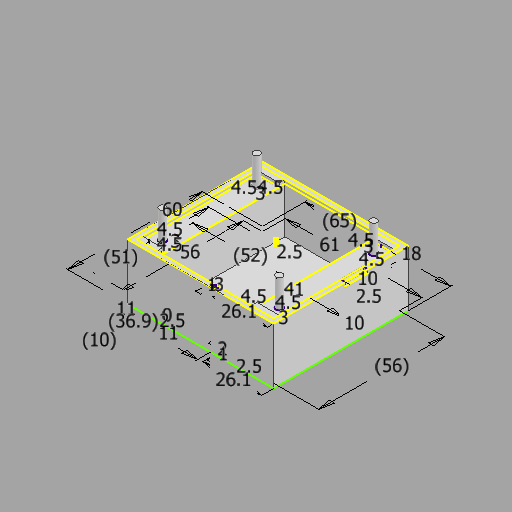
# Autodesk Inventor part: case
Saved by Autodesk Inventor 2027 (Build 310192000, 192)
## iProperties
Created: 2026-09-07
Part Number: case
Material: Generic
Document SubType Name: Modeling
Designer: jyjhm
Density: 1 g/cm^3
Appearance: Default
Author: jyjhm
Autodesk Inventor part; units mm, degrees
ref_plane "YZ Plane" through (0, 0, 0) normal (1, 0, 0) x (0, 1, 0)
ref_plane "XZ Plane" through (0, 0, 0) normal (0, 1, 0) x (-1, 0, 0)
ref_plane "XY Plane" through (0, 0, 0) normal (0, 0, 1) x (1, 0, 0)
sketch "Sketch1" plane through (0, 0, 0) normal (0, 1, 0) x (-1, 0, 0)
  line L0 (31.25, 31) -> (-29.75, 31)
  line L1 (-29.75, 31) -> (-29.75, -25)
  line L2 (-29.75, -25) -> (31.25, -25)
  line L3 (31.25, -25) -> (31.25, 31)
  line L4 (33.25, 33) -> (-31.75, 33)
  line L5 (-31.75, 33) -> (-31.75, -27)
  line L6 (-31.75, -27) -> (33.25, -27)
  line L7 (33.25, -27) -> (33.25, 33)
  line L8 (31.25, 31) -> (23.25, 31)
  line L9 (31.25, 23) -> (31.25, 31)
  line L10 (31.25, -25) -> (23.25, -25)
  line L11 (31.25, -17) -> (31.25, -25)
  line L12 (-29.75, 31) -> (-20.75, 31)
  line L13 (-29.75, 23) -> (-29.75, 31)
  line L14 (-29.75, -25) -> (-20.75, -25)
  line L15 (-29.75, -17) -> (-29.75, -25)
  line L16 (-3.65, 31) -> (-5.65, 31)
  line L17 (-5.65, 31) -> (-5.65, 32)
  line L18 (-5.65, 32) -> (-3.65, 32)
  line L19 (-3.65, 32) -> (-3.65, 31)
  line L20 (21.25, -25) -> (-19.75, -25)
  line L21 (-19.75, -25) -> (-19.75, 31)
  line L22 (-19.75, 31) -> (21.25, 31)
  line L23 (21.25, 31) -> (21.25, -25)
  line L24 (31.25, 31) -> (21.25, 31)
  line L25 (21.25, 31) -> (21.25, 28.5)
  line L26 (21.25, 28.5) -> (31.25, 28.5)
  line L27 (31.25, 28.5) -> (31.25, 31)
  line L28 (31.25, -25) -> (21.25, -25)
  line L29 (21.25, -25) -> (21.25, -22.5)
  line L30 (21.25, -22.5) -> (31.25, -22.5)
  line L31 (31.25, -22.5) -> (31.25, -25)
  line L32 (-29.75, 31) -> (-19.75, 31)
  line L33 (-19.75, 31) -> (-19.75, 28.5)
  line L34 (-19.75, 28.5) -> (-29.75, 28.5)
  line L35 (-29.75, 28.5) -> (-29.75, 31)
  line L36 (-29.75, -25) -> (-19.75, -25)
  line L37 (-19.75, -25) -> (-19.75, -22.5)
  line L38 (-19.75, -22.5) -> (-29.75, -22.5)
  line L39 (-29.75, -22.5) -> (-29.75, -25)
  line L40 (22.25, 31) -> (11.25, 31)
  line L41 (11.25, 31) -> (11.25, 33)
  line L42 (11.25, 33) -> (22.25, 33)
  line L43 (22.25, 33) -> (22.25, 31)
  line L44 (22.25, 28.5) -> (21.25, 28.5)
  line L45 (21.25, 28.5) -> (21.25, 31)
  line L46 (21.25, 31) -> (22.25, 31)
  line L47 (22.25, 31) -> (22.25, 28.5)
  point P0 (0, 0)
  point P1 (-29.75, 3)
  point P2 (21.25, 31)
  point P3 (-19.75, -25)
  point P4 (22.25, 32)
  dimension "d0" = 56
  dimension "d1" = 61
  dimension "d35" = 56
  dimension "d36" = 1
  dimension "d37" = 2
  dimension "d38" = 26.1
  dimension "d39" = 41
  dimension "d40" = 10
  dimension "d52" = 2.5
  dimension "d53" = 2.5
  dimension "d54" = 2.5
  dimension "d55" = 2.5
  dimension "d74" = 36.9
  dimension "d75" = 65
  dimension "d77" = 51
  dimension "d78" = 60
  dimension "d79" = 10
  dimension "d80" = 11
  dimension "d81" = 11
  dimension "d82" = 0
  constraints: 96 end point, 20 parallel, 14 horizontal, 10 perpendicular, 9 point on line, 2 midpoint
  measures "d0" distance of L2.end L0.start
  measures "d1" distance of L1.end L2.end
  measures "d35" distance between parallel lines of L0 L2
  measures "d36" distance of L16.end L17.end
  measures "d37" distance of L16.start L16.end
  measures "d38" distance between parallel lines of L5 L17
  measures "d39" distance between parallel lines of L21 L23
  measures "d40" distance between parallel lines of L1 L21
  measures "d52" distance between parallel lines of L0 L26
  measures "d53" distance between parallel lines of L2 L30
  measures "d54" distance between parallel lines of L0 L34
  measures "d55" distance from line of L14.end L38
  measures "d74" distance between parallel lines of L7 L19
  measures "d75" distance between parallel lines of L7 L5
  measures "d77" distance between parallel lines of L26 L30
  measures "d78" distance of L6.end L4.start
  measures "d79" distance between parallel lines of L3 L23
  measures "d80" distance from line of L7 point (22.25, 32)
  measures "d81" distance between parallel lines of L41 L43
  measures "d82" distance between parallel lines of L44 L26
extrude "Extrusion1" add sketch "Sketch1" along normal blind 3
extrude "Extrusion3" add sketch "Sketch1" along normal blind 25 contours L0 L43 L4 L7 L6 L5 L41 L19 L18 L17 L1 L2 L3 | L0 L41 L4 L43 | L0 L17 L18 L19
sketch "Sketch3" plane through (0, 25, 0) normal (0, 1, 0) x (1, 0, 0)
  line L0 (31.75, -33) -> (31.75, 27) projected
  line L1 (31.75, 27) -> (-33.25, 27) projected
  line L2 (-33.25, 27) -> (-33.25, -33) projected
  line L3 (-33.25, -33) -> (31.75, -33) projected
  line L4 (-31.25, -31) -> (-31.25, 25) projected
  line L5 (-31.25, 25) -> (29.75, 25) projected
  line L6 (29.75, 25) -> (29.75, -31) projected
  line L7 (29.75, -31) -> (-31.25, -31) projected
  line L8 (5.65, -31) -> (2.65, -31)
  line L9 (2.65, -31) -> (2.65, -32)
  line L10 (2.65, -32) -> (5.65, -32)
  line L11 (5.65, -32) -> (5.65, -31)
  line L12 (29.75, -1) -> (31.75, -1)
  line L13 (31.75, -1) -> (31.75, 9)
  line L14 (31.75, 9) -> (29.75, 9)
  line L15 (29.75, 9) -> (29.75, -1)
  point P0 (0, 0)
  point P1 (4.15, -32)
  dimension "d41" = 1
  dimension "d42" = 3
  dimension "d43" = 26.1
  dimension "d48" = 18
  dimension "d49" = 10
  constraints: 16 end point, 4 parallel, 3 point on line, 2 horizontal, 2 perpendicular, 1 midpoint
  measures "d41" distance from line of L3 point (4.15, -32)
  measures "d42" distance between parallel lines of L11 L9
  measures "d43" distance between parallel lines of L0 L11
  measures "d48" distance between parallel lines of L1 L14
  measures "d49" distance between parallel lines of L14 L12
extrude "Extrusion5" cut sketch "Sketch3" against normal blind 4 contours L11 L10 L9 L7
extrude "Extrusion6" add sketch "Sketch1" along normal blind 23.4 contours L3 L26 L47 L0 | L3 L30 L23 L26 | L47 L26 L23 L0 | L3 L2 L23 L30 | L2 L1 L38 L21 | L21 L34 L1 L0 | L38 L1 L34 L21
extrude "Extrusion7" cut sketch "Sketch3" against normal blind 1.6 contours L12 L6 L14 L0
sketch "Sketch4" plane through (0, 23.4, 0) normal (0, 1, 0) x (1, 0, 0)
  line L0 (-31.25, 25) -> (-21.25, 25) projected
  line L1 (-31.25, -31) -> (-31.25, 25) projected
  line L2 (-21.25, -31) -> (-31.25, -31) projected
  line L3 (-21.25, -31) -> (-21.25, 25) projected
  line L4 (29.75, -31) -> (19.75, -31) projected
  line L5 (29.75, -1) -> (29.75, -31) projected
  line L6 (31.75, -1) -> (29.75, -1) projected
  line L7 (31.75, 9) -> (31.75, -1) projected
  line L8 (29.75, 9) -> (31.75, 9) projected
  line L9 (29.75, 25) -> (29.75, 9) projected
  line L10 (19.75, 25) -> (29.75, 25) projected
  line L11 (19.75, 25) -> (19.75, -31) projected
  line L12 (19.75, -28.5) -> (29.75, -28.5) projected
  line L13 (-31.25, -31) -> (29.75, -31) projected
  line L14 (29.75, -31) -> (29.75, 25) projected
  line L15 (19.75, 25) -> (19.75, -31) projected
  line L16 (19.75, 22.5) -> (29.75, 22.5) projected
  line L17 (-21.25, -31) -> (-21.25, 25) projected
  line L18 (-21.25, -28.5) -> (-31.25, -28.5) projected
  line L19 (-31.25, 25) -> (-31.25, -31) projected
  line L20 (-21.25, 22.5) -> (-31.25, 22.5) projected
  line L21 (29.75, 25) -> (-31.25, 25) projected
  line L22 (-31.25, -31) -> (-21.25, -31)
  line L23 (-21.25, -31) -> (-21.25, -28.5)
  line L24 (-21.25, -28.5) -> (-31.25, -28.5)
  line L25 (-31.25, -28.5) -> (-31.25, -31)
  line L26 (-21.25, 22.5) -> (-31.25, 22.5)
  line L27 (-31.25, 22.5) -> (-31.25, 25)
  line L28 (-31.25, 25) -> (-21.25, 25)
  line L29 (-21.25, 25) -> (-21.25, 22.5)
  line L30 (19.75, -28.5) -> (29.75, -28.5)
  line L31 (29.75, -28.5) -> (29.75, -31)
  line L32 (29.75, -31) -> (19.75, -31)
  line L33 (19.75, -31) -> (19.75, -28.5)
  line L34 (29.75, 22.5) -> (19.75, 22.5)
  line L35 (19.75, 22.5) -> (19.75, 25)
  line L36 (19.75, 25) -> (29.75, 25)
  line L37 (29.75, 25) -> (29.75, 22.5)
  circle A0 centre (-26.75, 18) radius 1.5
  circle A1 centre (-26.75, -24) radius 1.5
  circle A2 centre (25.25, 18) radius 1.5
  circle A3 centre (25.25, -24) radius 1.5
  line L38 (29.75, 25) -> (29.75, 9) projected
  point P0 (0, 0)
  point P1 (24.75, 22.5)
  point P2 (29.75, 17)
  dimension "d58" = 4.5
  dimension "d59" = 4.5
  dimension "d60" = 3
  dimension "d61" = 4.5
  dimension "d62" = 4.5
  dimension "d63" = 3
  dimension "d66" = 4.5
  dimension "d67" = 4.5
  dimension "d68" = 3
  dimension "d69" = 4.5
  dimension "d70" = 4.5
  dimension "d71" = 3
  dimension "d87" = 52
  constraints: 32 end point, 8 parallel, 4 centre point, 4 horizontal, 4 perpendicular, 2 midpoint
  measures "d58" distance from line of L20 A0.centre
  measures "d59" distance from line of L1 A0.centre
  measures "d60" diameter of A0
  measures "d61" distance from line of L1 A1.centre
  measures "d62" distance from line of L24 A1.centre
  measures "d63" diameter of A1
  measures "d66" distance from line of L9 A2.centre
  measures "d67" distance from line of L16 A2.centre
  measures "d68" diameter of A2
  measures "d69" distance from line of L12 A3.centre
  measures "d70" distance from line of L14 A3.centre
  measures "d71" diameter of A3
  measures "d87" distance of A3.centre A1.centre
extrude "Extrusion8" add sketch "Sketch4" along normal blind 1.6 contours L0 L3 L20 L1 | L10 L9 L16 L11 | L18 L3 L2 L1 | L12 L5 L4 L11
extrude "Extrusion9" add sketch "Sketch4" along normal blind 12.6 contours A0 | A1 | A2 | A3
extrude "Extrusion10" cut sketch "Sketch1" along normal blind 25 contours L47 L26 L23 L0
extrude "Extrusion11" add sketch "Sketch1" along normal blind 23.4 contours L47 L26 L23 L0
body "Solid1"
